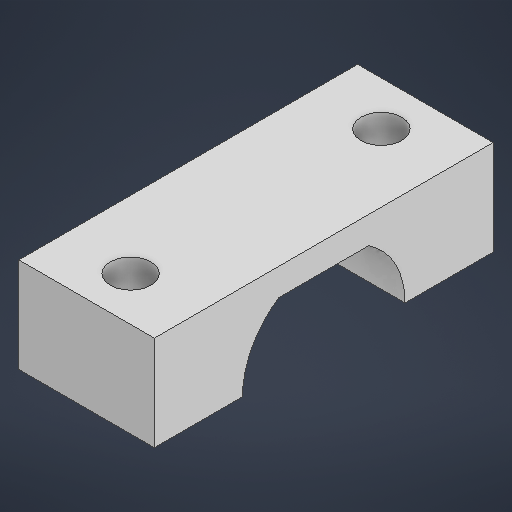
# Autodesk Inventor part: pump_mount
Saved by Autodesk Inventor 2027 (Build 310192000, 192)
## iProperties
Created: 2026-11-06
Part Number: pump_mount
Material: Generic
Document SubType Name: Modeling
Designer: Kasper
Density: 1 g/cm^3
Appearance: Default
Author: Kasper
Autodesk Inventor part; units mm, degrees
ref_plane "YZ Plane" through (0, 0, 0) normal (1, 0, 0) x (0, 1, 0)
ref_plane "XZ Plane" through (0, 0, 0) normal (0, 1, 0) x (-1, 0, 0)
ref_plane "XY Plane" through (0, 0, 0) normal (0, 0, 1) x (1, 0, 0)
sketch "Sketch1" plane through (0, 0, 0) normal (0, 1, 0) x (-1, 0, 0)
  point P0 (0, 0)
sketch "Sketch2" plane through (0, 0, 0) normal (1, 0, 0) x (0, 1, 0)
  line L0 (-3.5, -12.5) -> (3.5, -12.5)
  line L1 (3.5, -12.5) -> (3.5, 12.5)
  line L2 (3.5, 12.5) -> (-3.5, 12.5)
  line L3 (-3.5, -12.5) -> (3.5, 12.5) construction
  line L4 (3.5, -12.5) -> (-3.5, 12.5) construction
  line L5 (-3.5, 12.5) -> (-3.5, 6)
  line L6 (-3.5, -6) -> (-3.5, -12.5)
  line L7 (1.5, 3.3166) -> (1.5, -3.3166)
  arc A0 (-3.5, -6) -> (1.5, -3.3166) centre (-3.5, 0) ccw
  arc A1 (1.5, 3.3166) -> (-3.5, 6) centre (-3.5, 0) ccw
  point P0 (0, 0)
  point P1 (-0.5, 0)
  point P2 (3.5, 0)
  point P3 (1.5, 0)
  dimension "d0" = 25
  dimension "d1" = 7
  dimension "d4" = 5
  dimension "d5" = 6
  dimension "d6" = 6.6333
  constraints: 16 end point, 4 midpoint, 4 point on circle, 3 parallel, 2 centre point, 2 horizontal alignment, 1 concentric, 1 horizontal, 1 perpendicular, 1 vertical
  measures "d0" distance of L0.end L1.end
  measures "d1" distance of L1.end L2.end
  measures "d4" distance between parallel lines of L6 L7
  measures "d5" radius of A0
  measures "d6" distance of L7.start L7.end
extrude "Extrusion1" add sketch "Sketch2" along normal blind 10
sketch "Sketch3" plane through (0, -3.5, 6) normal (0, -1, 0) x (1, 0, 0)
  circle A0 centre (5, -15.25) radius 1.5
  circle A1 centre (5, 3.25) radius 1.5
  line L0 (10, -12) -> (10, -18.5) projected
  line L1 (0, -18.5) -> (10, -18.5) projected
  line L2 (0, 6.5) -> (10, 6.5) projected
  line L3 (10, 6.5) -> (10, 0) projected
  point P0 (0, -6)
  point P1 (10, -15.25)
  point P2 (5, -18.5)
  point P3 (5, 6.5)
  point P4 (10, 3.25)
  dimension "d9" = 3
  dimension "d10" = 3
  constraints: 4 midpoint, 2 centre point, 2 horizontal alignment, 2 vertical alignment
  measures "d9" diameter of A1
  measures "d10" diameter of A0
extrude "Extrusion2" cut sketch "Sketch3" against normal through all
body "Solid1"
